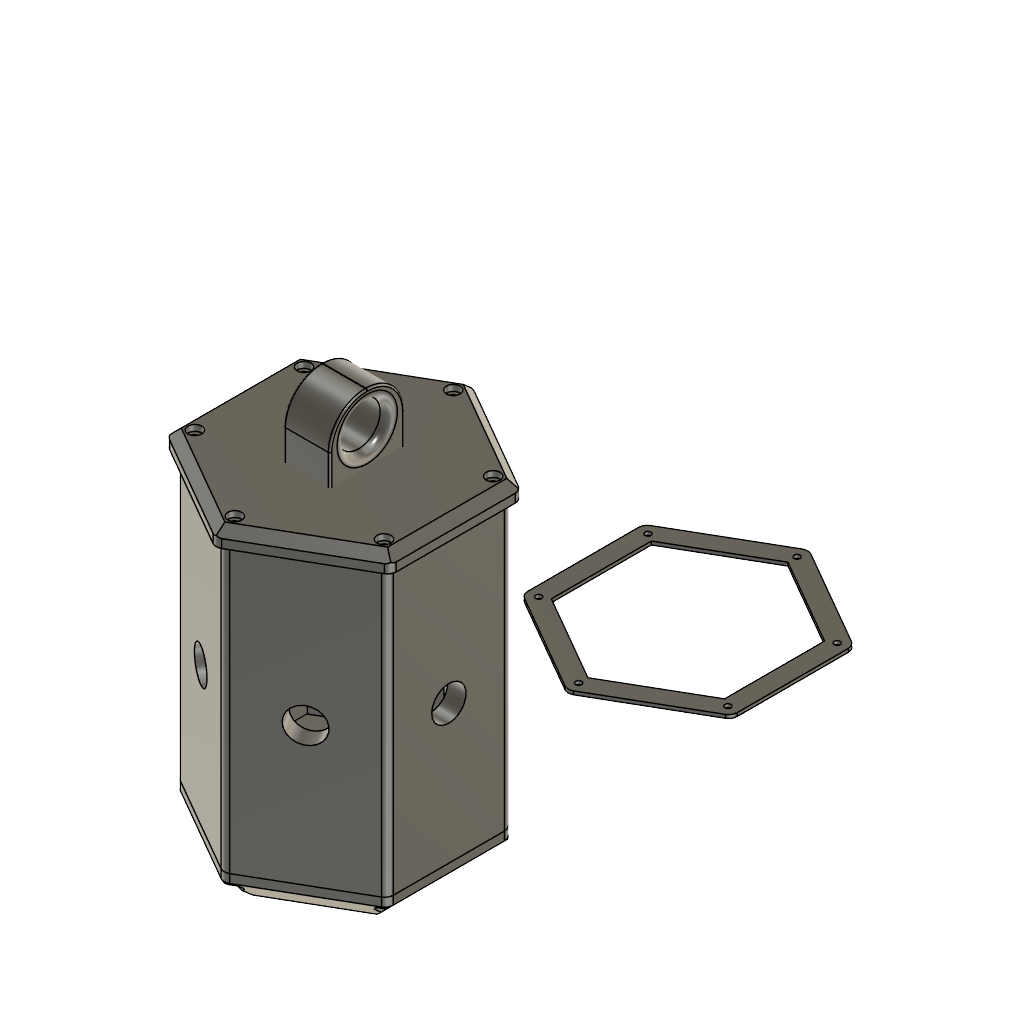
Meshcore 6 sided body  v2 (Autodesk Fusion 360 design; units mm, degrees)
part number: 2026-09-08-15-13-08-865
Autodesk Fusion 360 part; units mm, degrees
note: some values were not read from the file. Set by a fixed rule: which face or edge a step refers to.
sketch "Sketch5" plane through (0, 0, 0) normal (0, 0, 1) x (1, 0, 0)
  line L0 (61, 35.2184) -> (0, 70.4367)
  line L1 (0, 70.4367) -> (-61, 35.2184)
  line L2 (-61, 35.2184) -> (-61, -35.2184)
  line L3 (-61, -35.2184) -> (0, -70.4367)
  line L4 (0, -70.4367) -> (61, -35.2184)
  line L5 (61, -35.2184) -> (61, 35.2184)
  dimension "d4" = 61
  measures "d4" distance of origin L5
extrude "Extrude1" add sketch "Sketch5" along normal blind 5 makes body 1
sketch "Sketch7" plane through (0, 0, 0) normal (0, 0, 1) x (1, 0, 0)
  line L0 (50.1766, 29.3679) -> (-0.345, 58.1381)
  line L1 (-0.345, 58.1381) -> (-50.5216, 28.7703)
  line L2 (-50.5216, 28.7703) -> (-50.1766, -29.3679)
  line L3 (-50.1766, -29.3679) -> (0.345, -58.1381)
  line L4 (0.345, -58.1381) -> (50.5216, -28.7703)
  line L5 (50.5216, -28.7703) -> (50.1766, 29.3679)
  dimension "d7" = 50.35
  measures "d7" distance of origin L5
extrude "Extrude2" add sketch "Sketch7" along normal blind 10 separate body makes body 2
sketch "Sketch8" plane through (0, 0, 0) normal (0, 0, 1) x (1, 0, 0)
  line L0 (61, 35.2184) -> (0, 70.4367)
  line L1 (0, 70.4367) -> (-61, 35.2184)
  line L2 (-61, 35.2184) -> (-61, -35.2184)
  line L3 (-61, -35.2184) -> (0, -70.4367)
  line L4 (0, -70.4367) -> (61, -35.2184)
  line L5 (61, -35.2184) -> (61, 35.2184)
  line L6 (50.35, 29.0696) -> (0, 58.1392)
  line L7 (0, 58.1392) -> (-50.35, 29.0696)
  line L8 (-50.35, 29.0696) -> (-50.35, -29.0696)
  line L9 (-50.35, -29.0696) -> (0, -58.1392)
  line L10 (0, -58.1392) -> (50.35, -29.0696)
  line L11 (50.35, -29.0696) -> (50.35, 29.0696)
  dimension "d10" = 61
  dimension "d11" = 50.35
  measures "d10" distance of origin L5
  measures "d11" distance of origin L11
extrude "Extrude3" add sketch "Sketch8" along normal blind 50 separate body makes body 3
extrude "Extrude4" add 1 faces at (-20.3333, -54.5981, 50) along direction (0, 0, 1) blind 50 on bodies 3 bodies 3
move_body "Move1" bodies 3 to x (1, 0, 0) y (0, 1, 0) z (0, 0, 1) at (0, 0, 5)
combine "Combine1" operation add target body 1 tool bodies 2
sketch "Sketch9" plane through (0, 0, 0) normal (0, 0, 1) x (1, 0, 0)
  circle A0 centre (-75, 50) radius 1
  dimension "d16" = 2
  measures "d16" diameter of A0
sketch "Sketch10" plane through (0, 0, 0) normal (0, 0, 1) x (1, 0, 0)
  circle A0 centre (-75, 50) radius 2
  dimension "d19" = 4
  measures "d19" diameter of A0
combine "Combine2" [no effect]
sketch "Sketch11" plane through (0, 0, 0) normal (0, 0, 1) x (1, 0, 0)
  line L0 (-55, -31.7543) -> (0, -63.5085)
  line L1 (0, -63.5085) -> (55, -31.7543)
  line L2 (55, -31.7543) -> (55, 31.7543)
  line L3 (55, 31.7543) -> (0, 63.5085)
  line L4 (0, 63.5085) -> (-55, 31.7543)
  line L5 (-55, 31.7543) -> (-55, -31.7543)
sketch "Sketch12" plane through (0, 0, 0) normal (0, 0, 1) x (1, 0, 0)
  circle A0 centre (-25, 75) radius 1.75
  dimension "d27" = 3.5
  measures "d27" diameter of A0
extrude "Extrude8" add sketch "Sketch12" along normal blind 8 separate body makes body 4
extrude "Extrude9" add 1 faces at (-25.5014, 74.4125, 8) along direction (0, 0, 1) blind 15 on bodies 4 bodies 4
move_body "Move10" bodies 4 to x (1, 0, 0) y (0, 1, 0) z (0, 0, 1) at (25, -11.4915, -23)
sketch "Sketch13" plane through (0, 0, 0) normal (0, 0, 1) x (1, 0, 0)
  circle A0 centre (0, 63.5) radius 4
  dimension "d32" = 8
  measures "d32" diameter of A0
extrude "Extrude10" add sketch "Sketch13" along normal blind 4 separate body makes body 5
move_body "Move11" bodies 4 to x (1, 0, 0) y (0, 1, 0) z (0, 0, 1) at (0, 0, 23)
combine "Combine3" operation add target body 5 tool bodies 4 keep tools
combine "Combine4" operation add target body 5 tool bodies 4
move_body "Move12" bodies 5 to x (1, 0, 0) y (0, 1, 0) z (0, 0, 1) at (0, 0, -1.5)
copy_body "CopyPasteBodies5" bodies 5 makes body 6
move_body "Move13" bodies 6 to x (1, 0, 0) y (0, 1, 0) z (0, 0, 1) at (55, -31.7543, 0)
copy_body "CopyPasteBodies6" bodies 5 makes body 7
move_body "Move14" bodies 7 to x (1, 0, 0) y (0, 1, 0) z (0, 0, 1) at (55, -95.2628, 0)
copy_body "CopyPasteBodies7" bodies 5 makes body 8
move_body "Move15" bodies 8 to x (1, 0, 0) y (0, 1, 0) z (0, 0, 1) at (0, -127.0171, 0)
copy_body "CopyPasteBodies8" bodies 5 makes body 9
move_body "Move16" bodies 9 to x (1, 0, 0) y (0, 1, 0) z (0, 0, 1) at (-55, -95.2628, 0)
copy_body "CopyPasteBodies9" bodies 5 makes body 10
move_body "Move17" bodies 10 to x (1, 0, 0) y (0, 1, 0) z (0, 0, 1) at (-55, -31.7543, 0)
combine "Combine5" operation cut target body 1 tool bodies 5 6 10 7 8 9 keep tools
extrude "Extrude11" add 1 faces at (16.7255, 9.7893, 10) along direction (0, 0, 1) blind 5 on bodies 1 bodies 1
extrude "Extrude12" add 1 faces at (-34.817, 39.8971, 5) along direction (0, 0, 1) blind 5 on bodies 1 bodies 1
chamfer "Chamfer1" distance 5 angle 45 6 edges at (30.5, 52.8275, 0) (61, 0, 0) (30.5, -52.8275, 0) (-30.5, -52.8275, 0) (-61, 0, 0) (-30.5, 52.8275, 0) tangent chain off on bodies 1
extrude "Extrude13" add 1 faces at (-20.3333, -54.5981, 105) along direction (0, 0, 1) blind 71 on bodies 3 bodies 3
copy_body "CopyPasteBodies10" bodies 1 makes body 11
move_body "Move18" bodies 11 to x (1, 0, 0) y (0, 1, 0) z (0, 0, 1) at (0, 0, 171)
move_body "Move19" bodies 11 to x (-1, 0, 0) y (0, 1, 0) z (0, 0, -1) at (-122, 0, 352)
move_body "Move20" bodies 11 to x (1, 0, 0) y (0, 1, 0) z (0, 0, 1) at (122, 0.0012, -181)
move_body "Move21" bodies 11 to x (1, 0, 0) y (0, 1, 0) z (0, 0, 1) at (0, 0, 171)
move_body "Move22" bodies 11 to x (1, 0, 0) y (0, 1, 0) z (0, 0, 1) at (0, 0, 20)
move_body "Move23" bodies 11 to x (1, 0, 0) y (0, 1, 0) z (0, 0, 1) at (0, 0, -5)
copy_body "CopyPasteBodies11" bodies 5 10 9 8 6 7 makes body 12 makes body 13 makes body 14 makes body 15 makes body 16 makes body 17
move_body "Move24" bodies 12 13 14 15 16 17 to x (1, 0, 0) y (0, -1, 0) z (0, 0, -1) at (0, 127.0171, 5)
move_body "Move25" bodies 12 15 13 14 16 17 to x (1, 0, 0) y (0, 1, 0) z (0, 0, 1) at (0, -127.0256, 15)
move_body "Move26" bodies 12 15 13 14 16 17 to x (1, 0, 0) y (0, 1, 0) z (0, 0, 1) at (0, 0, 165)
combine "Combine6" operation cut target body 3 tool bodies 12 15 13 14 16 17 keep tools
extrude "Extrude14" add 1 faces at (-40.6667, 46.959, 177.6667) along direction (-0.5, 0.866025, 0) blind 2 on bodies 11 bodies 11
sketch "Sketch14" plane through (0, 0, 0) normal (0, 0, 1) x (1, 0, 0)
  line L0 (-65, -37.5278) -> (0, -75.0555)
  line L1 (0, -75.0555) -> (65, -37.5278)
  line L2 (65, -37.5278) -> (65, 37.5278)
  line L3 (65, 37.5278) -> (0, 75.0555)
  line L4 (0, 75.0555) -> (-65, 37.5278)
  line L5 (-65, 37.5278) -> (-65, -37.5278)
extrude "Extrude15" add sketch "Sketch14" along normal blind 10 separate body makes body 18
move_body "Move27" bodies 18 to x (1, 0, 0) y (0, 1, 0) z (0, 0, 1) at (0, 0, 171)
move_body "Move28" bodies 18 to x (1, 0, 0) y (0, 1, 0) z (0, 0, 1) at (0, 0, 5)
chamfer "Chamfer2" distance 5 angle 45 6 edges at (65, 0, 186) (32.5, -56.2917, 186) (-32.5, -56.2917, 186) (-65, 0, 186) (-32.5, 56.2917, 186) (32.5, 56.2917, 186) tangent chain off on bodies 18
combine "Combine7" operation cut target body 18 tool bodies 12 13 14 15 16 17 keep tools
sketch "Sketch15" plane through (0, 0, 0) normal (0, 0, 1) x (1, 0, 0)
  line L0 (21.5974, -13.5) -> (-21.5974, -13.5)
  line L1 (-21.5974, -13.5) -> (-21.5974, 13.5)
  line L2 (-21.5974, 13.5) -> (21.5974, 13.5)
  line L3 (21.5974, 13.5) -> (21.5974, -13.5)
  line L4 (21.5974, -13.5) -> (-21.5974, 13.5) construction
  line L5 (-21.5974, -13.5) -> (21.5974, 13.5) construction
  dimension "d48" = 27
  constraint horizontal L0
  constraint perpendicular L0 L1
  constraint parallel L0 L2
  constraint parallel L1 L3
  constraint coincident L4 origin
  constraint coincident L5 origin
  measures "d48" distance of L0.end L1.end
extrude "Extrude16" add sketch "Sketch15" along normal blind 20 separate body makes body 19
extrude "Extrude17" add 1 faces at (7.1991, -4.5, 20) along direction (0, 0, 1) blind 30 on bodies 19 bodies 19
move_body "Move29" bodies 19 to x (1, 0, 0) y (0, 1, 0) z (0, 0, 1) at (0, 0, 175)
sketch "Sketch16" plane through (0, 0, 0) normal (0, 1, 0) x (1, 0, 0)
  circle A0 centre (0, 0) radius 12.5
  dimension "d53" = 25
  constraint coincident A0.centre origin
  measures "d53" diameter of A0
extrude "Extrude18" add sketch "Sketch16" along normal blind 50 separate body makes body 20
extrude "Extrude19" cut 1 faces at (-41.6667, 48.6911, 177.6667) along direction (0.5, -0.866025, 0) blind 2 on bodies 11 bodies 11
move_body "Move30" bodies 20 to x (1, 0, 0) y (0, 1, 0) z (0, 0, 1) at (0, -25, 200)
move_body "Move31" bodies 20 to x (1, 0, 0) y (0, 1, 0) z (0, 0, 1) at (0, 0, 5)
fillet "Fillet1" radius 21.5 2 edges at (21.5974, 0, 225) (-21.5974, 0, 225) on bodies 19
combine "Combine8" operation cut target body 19 tool bodies 20 keep tools
extrude "Extrude21" cut 1 faces at (7.1991, -4.5, 175) along direction (0, 0, 1) blind 1 on bodies 19 bodies 19
sketch "Sketch17" plane through (0, 0, 0) normal (0, 0, 1) x (1, 0, 0)
  line L0 (120, -10) -> (80, -10)
  line L1 (80, -10) -> (80, 10)
  line L2 (80, 10) -> (120, 10)
  line L3 (120, 10) -> (120, -10)
  line L4 (120, -10) -> (80, 10) construction
  line L5 (80, -10) -> (120, 10) construction
  point P0 (100, 0)
  constraint horizontal L0
  constraint perpendicular L0 L1
  constraint parallel L0 L2
  constraint parallel L1 L3
  constraint coincident L4 P0
  constraint coincident L5 P0
extrude "Extrude22" add sketch "Sketch17" along normal blind 5 separate body makes body 21
extrude "Extrude23" cut 1 faces at (120, 3.3333, 1.6667) along direction (-1, 0, 0) blind 13 on bodies 21 bodies 21
extrude "Extrude24" add 1 faces at (-17.2044, -9.8838, 0) along direction (0, 0, -1) blind 10 on bodies 1 bodies 1
chamfer "Chamfer3" distance 10 angle 45 6 edges at (-56, -0.0085, -10) (-28.0037, 48.4953, -10) (28.0037, 48.4953, -10) (56, -0.0085, -10) (27.9963, -48.4996, -10) (-27.9963, -48.4996, -10) tangent chain off on bodies 1
sketch "Sketch18" plane through (0, 0, 0) normal (0, 0, 1) x (1, 0, 0)
  arc A0 (-160, 0) -> (-180, 0) centre (-170, 0) ccw
  arc A1 (-150, 0) -> (-190, 0) centre (-170, 0) ccw
  line L0 (-190, 0) -> (-180, 0)
  line L1 (-160, 0) -> (-150, 0)
  constraint coincident A0.centre A1.centre
  constraint perpendicular A0 L0
  constraint perpendicular A1 L1
extrude "Extrude25" add sketch "Sketch18" along normal blind 10 separate body makes body 22
move_body "Move32" bodies 22 to x (1, 0, 0) y (0, 0, -1) z (0, 1, 0) at (0, -5, 30)
move_body "Move33" bodies 22 to x (1, 0, 0) y (0, -1, 0) z (0, 0, -1) at (0, 10, 40)
move_body "Move34" bodies 22 to x (1, 0, 0) y (0, 1, 0) z (0, 0, 1) at (130, -10, -25)
move_body "Move35" bodies 22 to x (1, 0, 0) y (0, 1, 0) z (0, 0, 1) at (-5, 0, 0)
copy_body "CopyPasteBodies12" bodies 22 makes body 23
move_body "Move36" bodies 23 to x (1, 0, 0) y (0, 1, 0) z (0, 0, 1) at (90, 0, 0)
combine "Combine9" operation cut target body 1 tool bodies 23 22 keep tools
sketch "Sketch19" plane through (0, 0, 0) normal (0, 0, 1) x (1, 0, 0)
  circle A0 centre (200, -30) radius 2
  dimension "d73" = 4
  measures "d73" diameter of A0
extrude "Extrude26" add sketch "Sketch19" along normal blind 30 separate body makes body 24
extrude "Extrude27" add 1 faces at (200.6592, -30.2936, 30) along direction (0, 0, 1) blind 20 on bodies 24 bodies 24
copy_body "CopyPasteBodies13" bodies 24 makes body 25
move_body "Move37" bodies 25 to x (1, 0, 0) y (0, 1, 0) z (0, 0, 1) at (-10, 0, 0)
copy_body "CopyPasteBodies14" bodies 24 25 makes body 26 makes body 27
move_body "Move38" bodies 26 27 to x (1, 0, 0) y (0, 1, 0) z (0, 0, 1) at (0, 10, 0)
move_body "Move39" bodies 25 26 24 27 to x (1, 0, 0) y (0, 1, 0) z (0, 0, 1) at (-170, 10, 0)
move_body "Move40" bodies 26 27 25 24 to x (1, 0, 0) y (0, 1, 0) z (0, 0, 1) at (0, 0, -20)
move_body "Move41" bodies 24 25 26 27 to x (1, 0, 0) y (0, 1, 0) z (0, 0, 1) at (0, -5, 0)
copy_body "CopyPasteBodies15" bodies 24 25 26 27 makes body 28 makes body 29 makes body 30 makes body 31
move_body "Move42" bodies 28 29 30 31 to x (1, 0, 0) y (0, 1, 0) z (0, 0, 1) at (0, 40, 0)
copy_body "CopyPasteBodies16" bodies 24 28 29 25 26 27 31 30 makes body 32 makes body 33 makes body 34 makes body 35 makes body 36 makes body 37 makes body 38 makes body 39
move_body "Move43" bodies 32 33 34 35 36 37 38 39 to x (1, 0, 0) y (0, 1, 0) z (0, 0, 1) at (-50, 0, 0)
combine "Combine10" operation cut target body 1 tool bodies 24 28 29 32 34 33 36 38 37 35 25 26 27 39 31 30 keep tools
sketch "Sketch20" plane through (0, 0, 0) normal (0, 0, 1) x (1, 0, 0)
  circle A0 centre (0, 0) radius 8
  dimension "d78" = 16
  constraint coincident A0.centre origin
  measures "d78" diameter of A0
extrude "Extrude28" add sketch "Sketch20" along normal blind 50 separate body makes body 40
move_body "Move44" bodies 40 to x (1, 0, 0) y (0, 1, 0) z (0, 0, 1) at (0, 0, -25)
combine "Combine11" operation cut target body 1 tool bodies 40 keep tools
sketch "Sketch21" plane through (0, 0, 0) normal (0, 0, 1) x (1, 0, 0)
  circle A0 centre (0, 0) radius 21.5
  dimension "d81" = 43
  constraint coincident A0.centre origin
  measures "d81" diameter of A0
extrude "Extrude29" add sketch "Sketch21" along normal blind 40 separate body makes body 41
move_body "Move45" bodies 41 to x (1, 0, 0) y (0, 1, 0) z (0, 0, 1) at (0, 0, -40)
combine "Combine12" operation cut target body 1 tool bodies 41 keep tools
sketch "Sketch22" plane through (0, 0, 0) normal (0, 0, 1) x (1, 0, 0)
  line L0 (119.285, 2.5) -> (140.715, 2.5)
  line L1 (140.715, 2.5) -> (140.715, -2.5)
  line L2 (140.715, -2.5) -> (119.285, -2.5)
  line L3 (119.285, -2.5) -> (119.285, 2.5)
  line L4 (119.285, 2.5) -> (140.715, -2.5) construction
  line L5 (140.715, 2.5) -> (119.285, -2.5) construction
  point P0 (130, 0)
  dimension "d84" = 5
  constraint horizontal L0
  constraint perpendicular L0 L1
  constraint parallel L0 L2
  constraint parallel L1 L3
  constraint coincident L4 P0
  constraint coincident L5 P0
  measures "d84" distance of L0.end L1.end
extrude "Extrude30" add sketch "Sketch22" along normal blind 10 separate body makes body 42
move_body "Move46" bodies 42 to x (1, 0, 0) y (0, 1, 0) z (0, 0, 1) at (-130, 5, 0)
move_face "MoveFace1" by (0, 0, 5) 1 faces at (-3.5717, 5.8333, 10) on bodies 42
move_body "Move47" bodies 42 to x (1, 0, 0) y (0, 1, 0) z (0, 0, 1) at (0, 4, 0)
copy_body "CopyPasteBodies17" bodies 42 makes body 43
move_body "Move48" bodies 43 to x (1, 0, 0) y (0, 1, 0) z (0, 0, 1) at (0, -18, 0)
move_body "Move49" bodies 42 to x (1, 0, 0) y (0, 1, 0) z (0, 0, 1) at (0, 0.375, 0)
move_body "Move50" bodies 43 to x (1, 0, 0) y (0, 1, 0) z (0, 0, 1) at (0, -0.375, 0)
combine "Combine13" operation add target body 1 tool bodies 43 42 keep tools
move_body "Move51" bodies 19 to x (0, 1, 0) y (-1, 0, 0) z (0, 0, 1) at (0.0974, -0.0974, 0)
fillet "Fillet2" radius 2 16 edges at (-30.9874, -5, -10) (-36.3397, 0, -10) (-30.9874, 5, -10) (-25.6351, 0, -10) (-53.3912, -5, -2.6088) (-49.7823, 0, -6.2177) (-53.3912, 5, -2.6088) (-57, 0, 1) (25.6351, 0, -10) (36.3397, 0, -10) (30.9874, -5, -10) (30.9874, 5, -10) (53.3912, 5, -2.6088) (49.7823, 0, -6.2177) (57, 0, 1) (53.3912, -5, -2.6088) on bodies 1
move_face "OffsetFaces1" offset 1 6 faces at (-1.158, -64.8292, 176.1667) (-56.3406, -30.6379, 169.8333) (-56.3406, 30.6209, 176.1667) (53.6594, -30.6379, 169.8333) (-1.6445, 64.0985, 176.1667) (53.6594, 30.6209, 176.1667) on bodies 12 13 14 15 16 17
move_face "OffsetFaces2" offset 1 6 faces at (-1.158, -64.8206, 15.1667) (-56.3406, -30.6294, 8.8333) (56.3406, 32.8791, 8.8333) (-53.6594, 32.8791, 8.8333) (1.0216, 64.9294, 15.1667) (53.6594, -30.6294, 8.8333) on bodies 5 6 7 8 9 10
move_face "OffsetFaces3" offset -0.5 6 faces at (-56.3406, 30.6209, 171.8333) (-1.6445, 64.0985, 171.8333) (53.6594, 30.6209, 171.8333) (53.6594, -30.6379, 167.6667) (-1.158, -64.8292, 171.8333) (-56.3406, -30.6379, 167.6667) on bodies 3
sketch "Bottom Holes" plane through (0, 0, 5) normal (0, 0, -1) x (-1, 0, 0)
  line L0 (-50.35, -29.0696) -> (-50.35, 29.0696)
  line L1 (-50.35, 29.0696) -> (0, 58.1392)
  line L2 (0, 58.1392) -> (50.35, 29.0696)
  line L3 (50.35, 29.0696) -> (50.35, -29.0696)
  line L4 (50.35, -29.0696) -> (0, -58.1392)
  line L5 (0, -58.1392) -> (-50.35, -29.0696)
  line L6 (-61, 35.2184) -> (-61, -35.2184)
  line L7 (-61, -35.2184) -> (0, -70.4367)
  line L8 (0, -70.4367) -> (61, -35.2184)
  line L9 (61, -35.2184) -> (61, 35.2184)
  line L10 (61, 35.2184) -> (0, 70.4367)
  line L11 (0, 70.4367) -> (-61, 35.2184)
  circle A0 centre (-55, 31.75) radius 2
  circle A1 centre (-55, -31.76) radius 2
  circle A2 centre (55, 31.75) radius 2
  circle A3 centre (55, -31.76) radius 2
  circle A4 centre (0, 63.5) radius 2
  circle A5 centre (0, -63.52) radius 2
  dimension "d117" = 4
  dimension "d118" = 4
  dimension "d119" = 4
  dimension "d120" = 4
  dimension "d121" = 4
  dimension "d122" = 4
  measures "d117" diameter of A4
  measures "d118" diameter of A0
  measures "d119" diameter of A1
  measures "d120" diameter of A5
  measures "d121" diameter of A3
  measures "d122" diameter of A2
extrude "Bottom Holes Cut" cut sketch "Bottom Holes" against normal blind 12.5 contours A0 | A1 | A2 | A3 | A4 | A5 bodies 3
sketch "Side Hole 1" plane through (-61, 0, 0) normal (-1, 0, 0) x (0, -1, 0)
  line L0 (-35.2184, 5) -> (35.2184, 5)
  line L1 (35.2184, 5) -> (35.2184, 176)
  line L2 (35.2184, 176) -> (-35.2184, 176)
  line L3 (-35.2184, 176) -> (-35.2184, 5)
  circle A0 centre (0, 90.5) radius 10
  dimension "d207" = 20
  measures "d207" diameter of A0
extrude "Side Hole 15mm Cut" cut sketch "Side Hole 1" against normal blind 10.7 contours A0 bodies 3
sketch "Side Hole 2" plane through (-30.5, -52.8275, 0) normal (-0.5, -0.866025, 0) x (0.866025, -0.5, 0)
  line L0 (-35.2184, 5) -> (35.2184, 5)
  line L1 (35.2184, 5) -> (35.2184, 176)
  line L2 (35.2184, 176) -> (-35.2184, 176)
  line L3 (-35.2184, 176) -> (-35.2184, 5)
  circle A0 centre (0, 90.5) radius 10
  dimension "d208" = 20
  measures "d208" diameter of A0
extrude "Side Hole 15mm B Cut" cut sketch "Side Hole 2" against normal blind 10.7 contours A0 bodies 3
sketch "Side Hole 3" plane through (30.5, -52.8275, 0) normal (0.5, -0.866025, 0) x (0.866025, 0.5, 0)
  line L0 (-35.2184, 5) -> (35.2184, 5)
  line L1 (35.2184, 5) -> (35.2184, 176)
  line L2 (35.2184, 176) -> (-35.2184, 176)
  line L3 (-35.2184, 176) -> (-35.2184, 5)
  circle A0 centre (0, 90.5) radius 10
  dimension "d209" = 20
  measures "d209" diameter of A0
extrude "Side Hole 15mm Cut (0.5,-0.866)" cut sketch "Side Hole 3" against normal blind 10.7 contours A0 bodies 3
sketch "Side Hole 4" plane through (-30.5, 52.8275, 0) normal (-0.5, 0.866025, 0) x (-0.866025, -0.5, 0)
  line L0 (-35.2184, 5) -> (35.2184, 5)
  line L1 (35.2184, 5) -> (35.2184, 176)
  line L2 (35.2184, 176) -> (-35.2184, 176)
  line L3 (-35.2184, 176) -> (-35.2184, 5)
  circle A0 centre (0, 90.5) radius 10
  dimension "d210" = 20
  measures "d210" diameter of A0
extrude "Side Hole 15mm Cut (-0.5,0.866)" cut sketch "Side Hole 4" against normal blind 10.7 contours A0 bodies 3
sketch "Side Hole 5" plane through (30.5, 52.8275, 0) normal (0.5, 0.866025, 0) x (-0.866025, 0.5, 0)
  line L0 (-35.2184, 5) -> (35.2184, 5)
  line L1 (35.2184, 5) -> (35.2184, 176)
  line L2 (35.2184, 176) -> (-35.2184, 176)
  line L3 (-35.2184, 176) -> (-35.2184, 5)
  circle A0 centre (0, 90.5) radius 10
  dimension "d211" = 20
  measures "d211" diameter of A0
extrude "Side Hole 15mm Cut (0.5,0.866)" cut sketch "Side Hole 5" against normal blind 10.7 contours A0 bodies 3
sketch "Side Hole 6" plane through (61, 0, 0) normal (1, 0, 0) x (0, 1, 0)
  line L0 (-35.2184, 5) -> (35.2184, 5)
  line L1 (35.2184, 5) -> (35.2184, 176)
  line L2 (35.2184, 176) -> (-35.2184, 176)
  line L3 (-35.2184, 176) -> (-35.2184, 5)
  circle A0 centre (0, 90.5) radius 10
  dimension "d212" = 20
  measures "d212" diameter of A0
extrude "Side Hole 15mm Cut (1.0,-0.0)" cut sketch "Side Hole 6" against normal blind 10.7 contours A0 bodies 3
move_face "Bottom Thickness 10mm" offset -5 1 faces at (0.5356, 11.73, 0) on bodies 1
extrude "Extrude39" add 1 faces at (53.5739, -9.6955, 176) along direction (0, 0, 1) blind 2 separate body on bodies 3 makes body 44
move_body "Move52" bodies 44 to x (1, 0, 0) y (0, 1, 0) z (0, 0, 1) at (0, 200, 0)
move_body "Move53" bodies 44 to x (1, 0, 0) y (0, 1, 0) z (0, 0, 1) at (0, 0, -176)
move_face "OffsetFaces5" offset 0.5 1 faces at (-54.0746, 233.7966, 1.3333) on bodies 44
move_face "OffsetFaces6" offset 0.5 1 faces at (-2.2054, 263.9458, 1.3333) on bodies 44
move_face "OffsetFaces7" offset 0.5 1 faces at (53.9735, 229.7435, 1.3333) on bodies 44
move_face "OffsetFaces8" offset 0.5 1 faces at (53.9735, 166.235, 1.3333) on bodies 44
move_face "OffsetFaces9" offset 0.5 1 faces at (-56.0265, 166.235, 1.3333) on bodies 44
move_face "OffsetFaces10" offset 0.5 1 faces at (-1.2207, 138.373, 1.3333) on bodies 44
move_face "OffsetFaces11" offset 0.5 1 faces at (2.2472, 63.3878, 171.8333) on bodies 3
move_face "OffsetFaces12" offset -0.25 1 faces at (-1.6126, 64.1798, 167.6667) on bodies 3
move_face "OffsetFaces13" offset 0.25 1 faces at (-55.9254, 33.7966, 167.6667) on bodies 3
move_face "OffsetFaces14" offset 0.25 1 faces at (57.2388, -31.9868, 167.6667) on bodies 3
move_face "OffsetFaces15" offset 0.25 1 faces at (2.2388, -63.7411, 167.6667) on bodies 3
move_face "OffsetFaces16" offset 0.25 1 faces at (-52.7612, -31.9868, 167.6667) on bodies 3
move_face "OffsetFaces17" offset 0.05 1 faces at (-56.5943, 32.9533, 171.8333) on bodies 3
move_face "OffsetFaces18" offset 0.05 1 faces at (-1.7564, 64.4565, 167.6667) on bodies 3
move_face "OffsetFaces19" offset 0.05 1 faces at (54.0746, 33.7966, 167.6667) on bodies 3
move_face "OffsetFaces20" offset -0.1 1 faces at (57.1891, 31.5267, 167.6667) on bodies 3
move_face "OffsetFaces21" offset 0.2 1 faces at (57.1613, 32.5324, 167.6667) on bodies 3
move_face "OffsetFaces22" offset 0.15 1 faces at (57.0896, 31.5366, 167.6667) on bodies 3
move_face "OffsetFaces23" offset 0.05 1 faces at (-53.0025, -31.8625, 171.8333) on bodies 3
move_face "OffsetFaces24" offset 0.05 1 faces at (1.9901, -63.7162, 167.6667) on bodies 3
move_face "OffsetFaces25" offset 0.05 1 faces at (56.9975, -31.8625, 171.8333) on bodies 3
extrude "Extrude40" cut 1 faces at (0.5356, 11.73, 5) along direction (0, 0, 1) blind 2.5 on bodies 1 bodies 1
fillet "Fillet3" radius 5 1 edges at (61, -35.2184, 90.5) on bodies 3
fillet "Fillet4" radius 5 1 edges at (0, -70.4367, 90.5) on bodies 3
fillet "Fillet5" radius 5 1 edges at (0, 70.4367, 90.5) on bodies 3
fillet "Fillet6" radius 5 1 edges at (61, 35.2184, 90.5) on bodies 3
fillet "Fillet7" radius 5 1 edges at (-61, -35.2184, 90.5) on bodies 3
fillet "Fillet8" radius 5 1 edges at (-61, 35.2184, 90.5) on bodies 3
fillet "Fillet9" radius 5 1 edges at (61, 164.7816, 1) on bodies 44
fillet "Fillet10" radius 5 1 edges at (61, 235.2184, 1) on bodies 44
fillet "Fillet11" radius 5 1 edges at (0, 270.4367, 1) on bodies 44
fillet "Fillet12" radius 5 1 edges at (-61, 235.2184, 1) on bodies 44
fillet "Fillet13" radius 5 1 edges at (0, 129.5633, 1) on bodies 44
fillet "Fillet14" radius 5 1 edges at (-61, 164.7816, 1) on bodies 44
fillet "Fillet15" radius 5 1 edges at (61, -35.2184, 7.5) on bodies 1
fillet "Fillet16" radius 5 1 edges at (61, 35.2184, 7.5) on bodies 1
fillet "Fillet17" radius 5 1 edges at (-61, -35.2184, 7.5) on bodies 1
fillet "Fillet18" radius 5 1 edges at (0, -70.4367, 7.5) on bodies 1
fillet "Fillet19" radius 5 1 edges at (-61, 35.2184, 7.5) on bodies 1
fillet "Fillet20" radius 5 1 edges at (0, 70.4367, 7.5) on bodies 1
fillet "Fillet21" radius 5 1 edges at (0, 75.0555, 178.5) on bodies 18
fillet "Fillet22" radius 5 1 edges at (-65, 37.5278, 178.5) on bodies 18
fillet "Fillet23" radius 5 1 edges at (0, -75.0555, 178.5) on bodies 18
fillet "Fillet24" radius 5 1 edges at (-65, -37.5278, 178.5) on bodies 18
fillet "Fillet25" radius 5 1 edges at (65, -37.5278, 178.5) on bodies 18
fillet "Fillet26" radius 5 1 edges at (65, 37.5278, 178.5) on bodies 18
fillet "Fillet27" radius 5 1 edges at (13.5974, -11.7515, 209.5202) on bodies 19
fillet "Fillet28" radius 5 1 edges at (-13.4026, -11.7515, 200.4798) on bodies 19
fillet "Fillet29" radius 1 5 edges at (13.5974, -21.6949, 189.75) (13.5974, -15.3977, 218.7028) (13.5974, -0.0974, 225) (13.5974, 15.2028, 218.7028) (13.5974, 21.5, 189.75) on bodies 19
fillet "Fillet30" radius 1 5 edges at (-13.4026, 21.5, 189.75) (-13.4026, 15.2028, 218.7028) (-13.4026, -0.0974, 225) (-13.4026, -15.3977, 218.7028) (-13.4026, -21.6949, 189.75) on bodies 19
move_face "Top Holes 4mm" offset -0.05 6 faces at (53.1103, 32.2269, 167.6667) (56.9476, -31.86, 171.8333) (-56.8897, 32.2269, 167.6667) (-53.0524, -31.86, 171.8333) (1.9476, 63.4028, 171.8333) (1.9403, -63.7112, 167.6667) on bodies 3
sketch "Top Holes" plane through (0, 0, 176) normal (0, 0, 1) x (1, 0, 0)
  circle A0 centre (55, 31.7457) radius 2
  circle A1 centre (55, -31.7628) radius 2
  circle A2 centre (-55, 31.7457) radius 2
  circle A3 centre (-55, -31.7628) radius 2
  circle A4 centre (0, 63.5) radius 2
  circle A5 centre (0, -63.5171) radius 2
  line L0 (50.35, 29.0696) -> (50.35, -29.0696)
  line L1 (50.35, -29.0696) -> (0, -58.1392)
  line L2 (0, -58.1392) -> (-50.35, -29.0696)
  line L3 (-50.35, -29.0696) -> (-50.35, 29.0696)
  line L4 (-50.35, 29.0696) -> (0, 58.1392)
  line L5 (0, 58.1392) -> (50.35, 29.0696)
  arc A6 (-58.5, 36.6617) -> (-61, 32.3316) centre (-56, 32.3316) ccw
  line L6 (-61, 32.3316) -> (-61, -32.3316)
  arc A7 (-61, -32.3316) -> (-58.5, -36.6617) centre (-56, -32.3316) ccw
  line L7 (-58.5, -36.6617) -> (-2.5, -68.9934)
  arc A8 (-2.5, -68.9934) -> (2.5, -68.9934) centre (0, -64.6632) ccw
  line L8 (2.5, -68.9934) -> (58.5, -36.6617)
  arc A9 (58.5, -36.6617) -> (61, -32.3316) centre (56, -32.3316) ccw
  line L9 (61, -32.3316) -> (61, 32.3316)
  arc A10 (61, 32.3316) -> (58.5, 36.6617) centre (56, 32.3316) ccw
  line L10 (58.5, 36.6617) -> (2.5, 68.9934)
  arc A11 (2.5, 68.9934) -> (-2.5, 68.9934) centre (0, 64.6632) ccw
  line L11 (-2.5, 68.9934) -> (-58.5, 36.6617)
  circle A12 centre (55, 31.75) radius 2
  circle A13 centre (55, -31.76) radius 2
  circle A14 centre (-55, 31.75) radius 2
  circle A15 centre (-55, -31.76) radius 2
  circle A16 centre (0, 63.5) radius 2
  circle A17 centre (0, -63.52) radius 2
  dimension "d201" = 4
  dimension "d202" = 4
  dimension "d203" = 4
  dimension "d204" = 4
  dimension "d205" = 4
  dimension "d206" = 4
  constraint equal A12 A13
  constraint equal A12 A14
  constraint equal A12 A15
  constraint equal A12 A16
  constraint equal A12 A17
  measures "d201" diameter of A12
  measures "d202" diameter of A16
  measures "d203" diameter of A14
  measures "d204" diameter of A15
  measures "d205" diameter of A17
  measures "d206" diameter of A13
extrude "Top Holes Cut" cut sketch "Top Holes" against normal blind 12.5 contours A0 A12 | A1 A13 | A2 A14 | A3 A15 | A4 A16 | A5 A17 bodies 3
hidden bodies 11 21 40 41 42 43 20
equation "TopHoleDiameter = 4 mm" comment "Diameter of the six top holes"
named bodies: "Bottom", "Main Body", "Top", "Top v2", "One Inch Punch Out", "Bottom Rope cut out", "Bottom Rope cut out (1)", "Antenna Punch out", "Antenna Larg hole", "Gasket"
